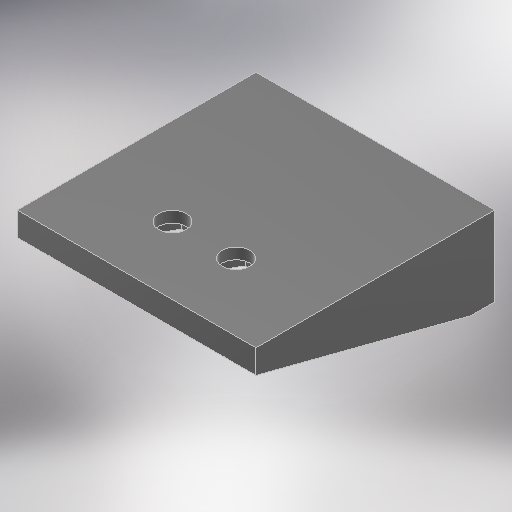
# Autodesk Inventor part: 3D_cable-mount
Saved by Autodesk Inventor 2025.3 (Build 293356030, 356C)
## iProperties
Created: 2026-09-02
Part Number: 3D_cable-mount
Material: 一般
Document SubType Name: Modeling
Designer: ibuki_ono
Density: 1 g/cm^3
Appearance: 滑らか - 黒
Author: ibuki_ono
Autodesk Inventor part; units mm, degrees
ref_plane "YZ Plane" through (0, 0, 0) normal (1, 0, 0) x (0, 1, 0)
ref_plane "XZ Plane" through (0, 0, 0) normal (0, 1, 0) x (-1, 0, 0)
ref_plane "XY Plane" through (0, 0, 0) normal (0, 0, 1) x (1, 0, 0)
sketch "スケッチ1" plane through (0, 0, 0) normal (0, 0, 1) x (1, 0, 0)
  line L0 (-15, -5) -> (15, -5)
  line L1 (15, -5) -> (15, 5)
  line L2 (15, 5) -> (-15, 5)
  line L3 (-15, 5) -> (-15, -5)
  line L4 (-15, -5) -> (15, 5) construction
  line L5 (15, -5) -> (-15, 5) construction
  point P0 (0, 0)
  dimension "d0" = 30
  dimension "d1" = 10
  constraints: 12 end point, 2 midpoint, 2 parallel, 1 horizontal, 1 perpendicular
  measures "d0" distance of L2.end L1.end
  measures "d1" distance of L1.end L0.end
extrude "押し出し1" add sketch "スケッチ1" along normal blind 3
sketch "スケッチ2" plane through (-15, 5, 0) normal (0, 1, 0) x (1, 0, 0)
  line L0 (30, 0) -> (0, 0) projected
  line L1 (0, 0) -> (0, -3) projected
  line L2 (30, -3) -> (0, -3) projected
  line L3 (30, 0) -> (30, -3) projected
  line L4 (30, -3) -> (0, -3)
  line L5 (0, -3) -> (0, -30)
  line L6 (0, -30) -> (30, -30)
  line L7 (30, -30) -> (30, -3)
  line L8 (30, 0) -> (30, -3) projected
  line L9 (0, 0) -> (0, -3) projected
  point P0 (15, 0)
  point P1 (0, -3)
  dimension "d5" = 30
  constraints: 8 end point, 3 point on line, 2 parallel, 1 horizontal, 1 perpendicular
  measures "d5" distance between parallel lines of L0 L6
extrude "押し出し2" add sketch "スケッチ2" against normal blind 3 contours L7 L6 L5 L2
sketch "スケッチ3" plane through (0, 0, 3) normal (0, 0, 1) x (1, 0, 0)
  line L0 (15, -5) -> (15, 2) projected
  line L1 (-15, 2) -> (-15, -5) projected
  line L2 (15, -1.5) -> (-15, -1.5) construction
  point P0 (0, 0)
  point P1 (7.5, -1.5)
  point P2 (-7.5, -1.5)
  dimension "d8" = 7.5
  dimension "d9" = 7.5
  constraints: 2 end point, 2 midpoint, 2 point on line
  measures "d8" horizontal distance of point (0, 0) point (7.5, -1.5)
  measures "d9" horizontal distance of point (0, 0) point (-7.5, -1.5)
hole "穴1" at (7.5, -1.5, 3) at (-7.5, -1.5, 3) direction (0, 0, -1) diameter 3.5 end through all counterbore diameter 6 counterbore depth 1
sketch "スケッチ4" plane through (15, -5, 0) normal (1, 0, 0) x (0, 0, -1)
  line L0 (0, 0) -> (0, 10) projected
  line L1 (0, 10) -> (-30, 10) projected
  line L2 (-30, 10) -> (-30, 7) projected
  line L3 (-3, 7) -> (-30, 7) projected
  line L4 (-3, 0) -> (-3, 7) projected
  line L5 (0, 0) -> (-3, 0) projected
  line L6 (-30, 7) -> (-3, 7) projected
  line L7 (-3, 0) -> (-30, 7)
  point P0 (0, 5)
  constraints: 2 end point
extrude "押し出し3" add sketch "スケッチ4" against normal blind 3 contours L7 L3 L4
mirror "ミラー1" about plane through (0, 0, 0) normal (1, 0, 0) of "押し出し3"
sketch "スケッチ5" plane through (-15, 2, 0) normal (0, -1, 0) x (1, 0, 0)
  line L0 (0, 30) -> (0, 3) projected
  line L1 (30, 30) -> (30, 3) projected
  line L2 (0, 21.5) -> (30, 21.5) construction
  line L3 (27, 30) -> (3, 30) construction
  point P0 (15, 0)
  point P1 (11, 21.5)
  point P2 (19, 21.5)
  point P3 (15, 21.5)
  dimension "d19" = 8.5
  dimension "d20" = 4
  dimension "d21" = 4
  constraints: 4 point on line, 2 end point, 1 midpoint, 1 perpendicular
  measures "d19" distance between parallel lines of L3 L2
  measures "d20" distance of point (15, 21.5) point (11, 21.5)
  measures "d21" distance of point (15, 21.5) point (19, 21.5)
hole "穴2" at (-4, 2, 21.5) at (4, 2, 21.5) direction (0, 1, 0) diameter 3.5 end through all
sketch "スケッチ6" plane through (-15, 2, 0) normal (0, -1, 0) x (1, 0, 0)
  circle A0 centre (11, 21.5) radius 1.75 projected
  line L0 (7.8246, 21.5) -> (9.4123, 24.25)
  line L1 (9.4123, 24.25) -> (12.5877, 24.25)
  line L2 (12.5877, 24.25) -> (14.1754, 21.5)
  line L3 (14.1754, 21.5) -> (12.5877, 18.75)
  line L4 (12.5877, 18.75) -> (9.4123, 18.75)
  line L5 (9.4123, 18.75) -> (7.8246, 21.5)
  point P0 (15, 0)
  dimension "d29" = 5.5
  constraints: 12 end point, 1 coincident, 1 horizontal alignment, 13 other
  measures "d29" distance between parallel lines of L4 L1
extrude "押し出し4" cut sketch "スケッチ6" against normal blind 1.6
mirror "ミラー2" about plane through (0, 0, 0) normal (1, 0, 0) of "押し出し4"
chamfer "面取り1" distance 1 angle 45 5 edges at (-12, -1.5, 3) (0, 2, 3) (-12, 2, 16.5) (12, 2, 16.5) (12, -1.5, 3)
equation "\"d9\" = d8"
equation "\"d21\" = d20"
